lp_support_parameter_study_v01_NOT_FOR_MANUFACTURE (Autodesk Fusion 360 design; units mm, degrees)
part number: 2026-11-07-02-04-41-200
part number: 2026-11-07-02-04-41-387
part number: 2026-11-07-02-04-41-607
part number: 2026-11-07-02-04-41-870
part number: 2026-11-07-02-04-42-158
part number: 2026-11-07-02-04-42-474
part number: 2026-11-07-02-04-42-832
Autodesk Fusion 360 part; units mm, degrees
sketch "スケッチ1" plane through (0, 0, 0) normal (0, 0, 1) x (1, 0, 0) in component "Opening_14_Lip_1p2"
  line L0 (-11, -11) -> (11, -11)
  line L1 (11, -11) -> (11, 11)
  line L2 (11, 11) -> (-11, 11)
  line L3 (-11, 11) -> (-11, -11)
  line L4 (-7, -7) -> (7, -7)
  line L5 (7, -7) -> (7, 7)
  line L6 (7, 7) -> (-7, 7)
  line L7 (-7, 7) -> (-7, -7)
  dimension "d9" = 11
  dimension "d10" = 11
  dimension "d11" = 22
  dimension "d12" = 22
  dimension "d13" = 7
  dimension "d14" = 7
  dimension "d15" = 14
  dimension "d16" = 14
  constraint horizontal L0
  constraint horizontal L2
  constraint vertical L1
  constraint vertical L3
  constraint horizontal L4
  constraint horizontal L6
  constraint vertical L5
  constraint vertical L7
  measures "d9" horizontal distance of origin L0.start
  measures "d10" vertical distance of origin L0.start
  measures "d11" horizontal distance of L0.start L0.end
  measures "d12" vertical distance of L0.end L1.end
  measures "d13" horizontal distance of origin L4.start
  measures "d14" vertical distance of origin L4.start
  measures "d15" horizontal distance of L4.start L4.end
  measures "d16" vertical distance of L4.end L5.end
extrude "Frame_with_through_opening" add sketch "スケッチ1" along normal blind 3 makes body 1 in component "Opening_14_Lip_1p2"
sketch "スケッチ2" plane through (0, 0, 0) normal (0, 0, 1) x (1, 0, 0) in component "Opening_14_Lip_1p2"
  line L0 (-9, -9) -> (9, -9)
  line L1 (9, -9) -> (9, 9)
  line L2 (9, 9) -> (-9, 9)
  line L3 (-9, 9) -> (-9, -9)
  dimension "d19" = 9
  dimension "d20" = 9
  dimension "d21" = 18
  dimension "d22" = 18
  constraint horizontal L0
  constraint horizontal L2
  constraint vertical L1
  constraint vertical L3
  measures "d19" horizontal distance of origin L0.start
  measures "d20" vertical distance of origin L0.start
  measures "d21" horizontal distance of L0.start L0.end
  measures "d22" vertical distance of L0.end L1.end
extrude "Underside_pocket_lip_1.2mm" cut sketch "スケッチ2" along normal blind 1.8 bodies 1 in component "Opening_14_Lip_1p2"
sketch "スケッチ1 (2)" plane through (0, 0, 0) normal (0, 0, 1) x (1, 0, 0) in component "Opening_14p1_Lip_1p2"
  line L0 (-11, -11) -> (11, -11)
  line L1 (11, -11) -> (11, 11)
  line L2 (11, 11) -> (-11, 11)
  line L3 (-11, 11) -> (-11, -11)
  line L4 (-7.05, -7.05) -> (7.05, -7.05)
  line L5 (7.05, -7.05) -> (7.05, 7.05)
  line L6 (7.05, 7.05) -> (-7.05, 7.05)
  line L7 (-7.05, 7.05) -> (-7.05, -7.05)
  dimension "d25" = 11
  dimension "d26" = 11
  dimension "d27" = 22
  dimension "d28" = 22
  dimension "d29" = 7.05
  dimension "d30" = 7.05
  dimension "d31" = 14.1
  dimension "d32" = 14.1
  constraint horizontal L0
  constraint horizontal L2
  constraint vertical L1
  constraint vertical L3
  constraint horizontal L4
  constraint horizontal L6
  constraint vertical L5
  constraint vertical L7
  measures "d25" horizontal distance of origin L0.start
  measures "d26" vertical distance of origin L0.start
  measures "d27" horizontal distance of L0.start L0.end
  measures "d28" vertical distance of L0.end L1.end
  measures "d29" horizontal distance of origin L4.start
  measures "d30" vertical distance of origin L4.start
  measures "d31" horizontal distance of L4.start L4.end
  measures "d32" vertical distance of L4.end L5.end
extrude "Frame_with_through_opening'" add sketch "スケッチ1 (2)" along normal blind 3 separate body makes body 2 in component "Opening_14p1_Lip_1p2"
sketch "スケッチ2 (2)" plane through (0, 0, 0) normal (0, 0, 1) x (1, 0, 0) in component "Opening_14p1_Lip_1p2"
  line L0 (-9, -9) -> (9, -9)
  line L1 (9, -9) -> (9, 9)
  line L2 (9, 9) -> (-9, 9)
  line L3 (-9, 9) -> (-9, -9)
  dimension "d35" = 9
  dimension "d36" = 9
  dimension "d37" = 18
  dimension "d38" = 18
  constraint horizontal L0
  constraint horizontal L2
  constraint vertical L1
  constraint vertical L3
  measures "d35" horizontal distance of origin L0.start
  measures "d36" vertical distance of origin L0.start
  measures "d37" horizontal distance of L0.start L0.end
  measures "d38" vertical distance of L0.end L1.end
extrude "Underside_pocket_lip_1.2mm'" cut sketch "スケッチ2 (2)" along normal blind 1.8 bodies 2 in component "Opening_14p1_Lip_1p2"
sketch "スケッチ1 (3)" plane through (0, 0, 0) normal (0, 0, 1) x (1, 0, 0) in component "Opening_14p2_Lip_1p2"
  line L0 (-11, -11) -> (11, -11)
  line L1 (11, -11) -> (11, 11)
  line L2 (11, 11) -> (-11, 11)
  line L3 (-11, 11) -> (-11, -11)
  line L4 (-7.1, -7.1) -> (7.1, -7.1)
  line L5 (7.1, -7.1) -> (7.1, 7.1)
  line L6 (7.1, 7.1) -> (-7.1, 7.1)
  line L7 (-7.1, 7.1) -> (-7.1, -7.1)
  dimension "d41" = 11
  dimension "d42" = 11
  dimension "d43" = 22
  dimension "d44" = 22
  dimension "d45" = 7.1
  dimension "d46" = 7.1
  dimension "d47" = 14.2
  dimension "d48" = 14.2
  constraint horizontal L0
  constraint horizontal L2
  constraint vertical L1
  constraint vertical L3
  constraint horizontal L4
  constraint horizontal L6
  constraint vertical L5
  constraint vertical L7
  measures "d41" horizontal distance of origin L0.start
  measures "d42" vertical distance of origin L0.start
  measures "d43" horizontal distance of L0.start L0.end
  measures "d44" vertical distance of L0.end L1.end
  measures "d45" horizontal distance of origin L4.start
  measures "d46" vertical distance of origin L4.start
  measures "d47" horizontal distance of L4.start L4.end
  measures "d48" vertical distance of L4.end L5.end
extrude "Frame_with_through_opening''" add sketch "スケッチ1 (3)" along normal blind 3 separate body makes body 3 in component "Opening_14p2_Lip_1p2"
sketch "スケッチ2 (3)" plane through (0, 0, 0) normal (0, 0, 1) x (1, 0, 0) in component "Opening_14p2_Lip_1p2"
  line L0 (-9, -9) -> (9, -9)
  line L1 (9, -9) -> (9, 9)
  line L2 (9, 9) -> (-9, 9)
  line L3 (-9, 9) -> (-9, -9)
  dimension "d51" = 9
  dimension "d52" = 9
  dimension "d53" = 18
  dimension "d54" = 18
  constraint horizontal L0
  constraint horizontal L2
  constraint vertical L1
  constraint vertical L3
  measures "d51" horizontal distance of origin L0.start
  measures "d52" vertical distance of origin L0.start
  measures "d53" horizontal distance of L0.start L0.end
  measures "d54" vertical distance of L0.end L1.end
extrude "Underside_pocket_lip_1.2mm''" cut sketch "スケッチ2 (3)" along normal blind 1.8 bodies 3 in component "Opening_14p2_Lip_1p2"
sketch "スケッチ1 (4)" plane through (0, 0, 0) normal (0, 0, 1) x (1, 0, 0) in component "Opening_14_Lip_1p3"
  line L0 (-11, -11) -> (11, -11)
  line L1 (11, -11) -> (11, 11)
  line L2 (11, 11) -> (-11, 11)
  line L3 (-11, 11) -> (-11, -11)
  line L4 (-7, -7) -> (7, -7)
  line L5 (7, -7) -> (7, 7)
  line L6 (7, 7) -> (-7, 7)
  line L7 (-7, 7) -> (-7, -7)
  dimension "d57" = 11
  dimension "d58" = 11
  dimension "d59" = 22
  dimension "d60" = 22
  dimension "d61" = 7
  dimension "d62" = 7
  dimension "d63" = 14
  dimension "d64" = 14
  constraint horizontal L0
  constraint horizontal L2
  constraint vertical L1
  constraint vertical L3
  constraint horizontal L4
  constraint horizontal L6
  constraint vertical L5
  constraint vertical L7
  measures "d57" horizontal distance of origin L0.start
  measures "d58" vertical distance of origin L0.start
  measures "d59" horizontal distance of L0.start L0.end
  measures "d60" vertical distance of L0.end L1.end
  measures "d61" horizontal distance of origin L4.start
  measures "d62" vertical distance of origin L4.start
  measures "d63" horizontal distance of L4.start L4.end
  measures "d64" vertical distance of L4.end L5.end
extrude "Frame_with_through_opening'''" add sketch "スケッチ1 (4)" along normal blind 3 separate body makes body 4 in component "Opening_14_Lip_1p3"
sketch "スケッチ2 (4)" plane through (0, 0, 0) normal (0, 0, 1) x (1, 0, 0) in component "Opening_14_Lip_1p3"
  line L0 (-9, -9) -> (9, -9)
  line L1 (9, -9) -> (9, 9)
  line L2 (9, 9) -> (-9, 9)
  line L3 (-9, 9) -> (-9, -9)
  dimension "d67" = 9
  dimension "d68" = 9
  dimension "d69" = 18
  dimension "d70" = 18
  constraint horizontal L0
  constraint horizontal L2
  constraint vertical L1
  constraint vertical L3
  measures "d67" horizontal distance of origin L0.start
  measures "d68" vertical distance of origin L0.start
  measures "d69" horizontal distance of L0.start L0.end
  measures "d70" vertical distance of L0.end L1.end
extrude "Underside_pocket_lip_1.3mm" cut sketch "スケッチ2 (4)" along normal blind 1.7 bodies 4 in component "Opening_14_Lip_1p3"
sketch "スケッチ1 (5)" plane through (0, 0, 0) normal (0, 0, 1) x (1, 0, 0) in component "Opening_14p1_Lip_1p3"
  line L0 (-11, -11) -> (11, -11)
  line L1 (11, -11) -> (11, 11)
  line L2 (11, 11) -> (-11, 11)
  line L3 (-11, 11) -> (-11, -11)
  line L4 (-7.05, -7.05) -> (7.05, -7.05)
  line L5 (7.05, -7.05) -> (7.05, 7.05)
  line L6 (7.05, 7.05) -> (-7.05, 7.05)
  line L7 (-7.05, 7.05) -> (-7.05, -7.05)
  dimension "d73" = 11
  dimension "d74" = 11
  dimension "d75" = 22
  dimension "d76" = 22
  dimension "d77" = 7.05
  dimension "d78" = 7.05
  dimension "d79" = 14.1
  dimension "d80" = 14.1
  constraint horizontal L0
  constraint horizontal L2
  constraint vertical L1
  constraint vertical L3
  constraint horizontal L4
  constraint horizontal L6
  constraint vertical L5
  constraint vertical L7
  measures "d73" horizontal distance of origin L0.start
  measures "d74" vertical distance of origin L0.start
  measures "d75" horizontal distance of L0.start L0.end
  measures "d76" vertical distance of L0.end L1.end
  measures "d77" horizontal distance of origin L4.start
  measures "d78" vertical distance of origin L4.start
  measures "d79" horizontal distance of L4.start L4.end
  measures "d80" vertical distance of L4.end L5.end
extrude "Frame_with_through_opening''''" add sketch "スケッチ1 (5)" along normal blind 3 separate body makes body 5 in component "Opening_14p1_Lip_1p3"
sketch "スケッチ2 (5)" plane through (0, 0, 0) normal (0, 0, 1) x (1, 0, 0) in component "Opening_14p1_Lip_1p3"
  line L0 (-9, -9) -> (9, -9)
  line L1 (9, -9) -> (9, 9)
  line L2 (9, 9) -> (-9, 9)
  line L3 (-9, 9) -> (-9, -9)
  dimension "d83" = 9
  dimension "d84" = 9
  dimension "d85" = 18
  dimension "d86" = 18
  constraint horizontal L0
  constraint horizontal L2
  constraint vertical L1
  constraint vertical L3
  measures "d83" horizontal distance of origin L0.start
  measures "d84" vertical distance of origin L0.start
  measures "d85" horizontal distance of L0.start L0.end
  measures "d86" vertical distance of L0.end L1.end
extrude "Underside_pocket_lip_1.3mm'" cut sketch "スケッチ2 (5)" along normal blind 1.7 bodies 5 in component "Opening_14p1_Lip_1p3"
sketch "スケッチ1 (6)" plane through (0, 0, 0) normal (0, 0, 1) x (1, 0, 0) in component "Opening_14p2_Lip_1p3"
  line L0 (-11, -11) -> (11, -11)
  line L1 (11, -11) -> (11, 11)
  line L2 (11, 11) -> (-11, 11)
  line L3 (-11, 11) -> (-11, -11)
  line L4 (-7.1, -7.1) -> (7.1, -7.1)
  line L5 (7.1, -7.1) -> (7.1, 7.1)
  line L6 (7.1, 7.1) -> (-7.1, 7.1)
  line L7 (-7.1, 7.1) -> (-7.1, -7.1)
  dimension "d89" = 11
  dimension "d90" = 11
  dimension "d91" = 22
  dimension "d92" = 22
  dimension "d93" = 7.1
  dimension "d94" = 7.1
  dimension "d95" = 14.2
  dimension "d96" = 14.2
  constraint horizontal L0
  constraint horizontal L2
  constraint vertical L1
  constraint vertical L3
  constraint horizontal L4
  constraint horizontal L6
  constraint vertical L5
  constraint vertical L7
  measures "d89" horizontal distance of origin L0.start
  measures "d90" vertical distance of origin L0.start
  measures "d91" horizontal distance of L0.start L0.end
  measures "d92" vertical distance of L0.end L1.end
  measures "d93" horizontal distance of origin L4.start
  measures "d94" vertical distance of origin L4.start
  measures "d95" horizontal distance of L4.start L4.end
  measures "d96" vertical distance of L4.end L5.end
extrude "Frame_with_through_opening'''''" add sketch "スケッチ1 (6)" along normal blind 3 separate body makes body 6 in component "Opening_14p2_Lip_1p3"
sketch "スケッチ2 (6)" plane through (0, 0, 0) normal (0, 0, 1) x (1, 0, 0) in component "Opening_14p2_Lip_1p3"
  line L0 (-9, -9) -> (9, -9)
  line L1 (9, -9) -> (9, 9)
  line L2 (9, 9) -> (-9, 9)
  line L3 (-9, 9) -> (-9, -9)
  dimension "d99" = 9
  dimension "d100" = 9
  dimension "d101" = 18
  dimension "d102" = 18
  constraint horizontal L0
  constraint horizontal L2
  constraint vertical L1
  constraint vertical L3
  measures "d99" horizontal distance of origin L0.start
  measures "d100" vertical distance of origin L0.start
  measures "d101" horizontal distance of L0.start L0.end
  measures "d102" vertical distance of L0.end L1.end
extrude "Underside_pocket_lip_1.3mm''" cut sketch "スケッチ2 (6)" along normal blind 1.7 bodies 6 in component "Opening_14p2_Lip_1p3"
component "Opening_14_Lip_1p2" placed x (1, 0, 0) y (0, 1, 0) z (0, 0, 1) at (0, 0, 0)
component "Opening_14p1_Lip_1p2" placed x (1, 0, 0) y (0, 1, 0) z (0, 0, 1) at (30, 0, 0)
component "Opening_14p2_Lip_1p2" placed x (1, 0, 0) y (0, 1, 0) z (0, 0, 1) at (60, 0, 0)
component "Opening_14_Lip_1p3" placed x (1, 0, 0) y (0, 1, 0) z (0, 0, 1) at (0, 30, 0)
component "Opening_14p1_Lip_1p3" placed x (1, 0, 0) y (0, 1, 0) z (0, 0, 1) at (30, 30, 0)
component "Opening_14p2_Lip_1p3" placed x (1, 0, 0) y (0, 1, 0) z (0, 0, 1) at (60, 30, 0)
equation "coupon_width = 22 mm" comment "Provisional comparison dimension; fit unverified"
equation "frame_height = 3 mm" comment "Provisional comparison dimension; fit unverified"
equation "underside_relief = 18 mm" comment "Provisional comparison dimension; fit unverified"
equation "opening_small = 14 mm" comment "Provisional comparison dimension; fit unverified"
equation "opening_middle = 14.1 mm" comment "Provisional comparison dimension; fit unverified"
equation "opening_large = 14.2 mm" comment "Provisional comparison dimension; fit unverified"
equation "lip_thin = 1.2 mm" comment "Provisional comparison dimension; fit unverified"
equation "lip_thick = 1.3 mm" comment "Provisional comparison dimension; fit unverified"
equation "d9 = coupon_width / 2"
equation "d10 = coupon_width / 2"
equation "d11 = coupon_width"
equation "d12 = coupon_width"
equation "d13 = opening_small / 2"
equation "d14 = opening_small / 2"
equation "d15 = opening_small"
equation "d16 = opening_small"
equation "d17 = frame_height"
equation "d19 = underside_relief / 2"
equation "d20 = underside_relief / 2"
equation "d21 = underside_relief"
equation "d22 = underside_relief"
equation "d23 = frame_height - lip_thin"
equation "d25 = coupon_width / 2"
equation "d26 = coupon_width / 2"
equation "d27 = coupon_width"
equation "d28 = coupon_width"
equation "d29 = opening_middle / 2"
equation "d30 = opening_middle / 2"
equation "d31 = opening_middle"
equation "d32 = opening_middle"
equation "d33 = frame_height"
equation "d35 = underside_relief / 2"
equation "d36 = underside_relief / 2"
equation "d37 = underside_relief"
equation "d38 = underside_relief"
equation "d39 = frame_height - lip_thin"
equation "d41 = coupon_width / 2"
equation "d42 = coupon_width / 2"
equation "d43 = coupon_width"
equation "d44 = coupon_width"
equation "d45 = opening_large / 2"
equation "d46 = opening_large / 2"
equation "d47 = opening_large"
equation "d48 = opening_large"
equation "d49 = frame_height"
equation "d51 = underside_relief / 2"
equation "d52 = underside_relief / 2"
equation "d53 = underside_relief"
equation "d54 = underside_relief"
equation "d55 = frame_height - lip_thin"
equation "d57 = coupon_width / 2"
equation "d58 = coupon_width / 2"
equation "d59 = coupon_width"
equation "d60 = coupon_width"
equation "d61 = opening_small / 2"
equation "d62 = opening_small / 2"
equation "d63 = opening_small"
equation "d64 = opening_small"
equation "d65 = frame_height"
equation "d67 = underside_relief / 2"
equation "d68 = underside_relief / 2"
equation "d69 = underside_relief"
equation "d70 = underside_relief"
equation "d71 = frame_height - lip_thick"
equation "d73 = coupon_width / 2"
equation "d74 = coupon_width / 2"
equation "d75 = coupon_width"
equation "d76 = coupon_width"
equation "d77 = opening_middle / 2"
equation "d78 = opening_middle / 2"
equation "d79 = opening_middle"
equation "d80 = opening_middle"
equation "d81 = frame_height"
equation "d83 = underside_relief / 2"
equation "d84 = underside_relief / 2"
equation "d85 = underside_relief"
equation "d86 = underside_relief"
equation "d87 = frame_height - lip_thick"
equation "d89 = coupon_width / 2"
equation "d90 = coupon_width / 2"
equation "d91 = coupon_width"
equation "d92 = coupon_width"
equation "d93 = opening_large / 2"
equation "d94 = opening_large / 2"
equation "d95 = opening_large"
equation "d96 = opening_large"
equation "d97 = frame_height"
equation "d99 = underside_relief / 2"
equation "d100 = underside_relief / 2"
equation "d101 = underside_relief"
equation "d102 = underside_relief"
equation "d103 = frame_height - lip_thick"
